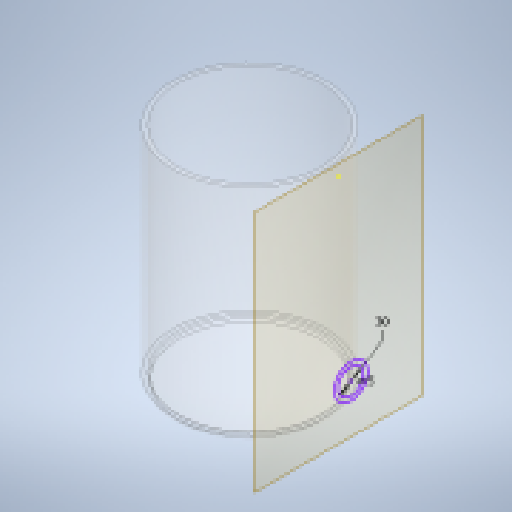
# Autodesk Inventor part: TANQUE
Saved by Autodesk Inventor 2025 (Build 290162000, 162)
## iProperties
Created: 2026-10-05
Part Number: TANQUE
Material: Plástico, transparente
Document SubType Name: Modeling
Designer: Projeto
Density: 1.188 g/cm^3
Appearance: Transparente - Claro
Author: Projeto
Autodesk Inventor part; units mm, degrees
ref_plane "XZ Plane" through (0, 0, 0) normal (0, 1, 0) x (-1, 0, 0)
ref_plane "XY Plane" through (0, 0, 0) normal (0, 0, 1) x (1, 0, 0)
sketch "Esboço1" plane through (0, 0, 0) normal (0, 0, 1) x (1, 0, 0)
  line L0 (-85, 0) -> (-85, -253)
  arc A0 (-85, -253) -> (-83, -255) centre (-83, -253) ccw
  line L1 (-83, -255) -> (0, -255)
  line L2 (-90, 0) -> (-90, -253)
  arc A1 (-90, -253) -> (-83, -260) centre (-83, -253) ccw
  line L3 (-83, -260) -> (0, -260)
  line L4 (0, -260) -> (0, -255)
  line L5 (0, -255) -> (0, 0) construction
  line L6 (-90, 0) -> (-85, 0)
  dimension "d0" = 5
  dimension "d1" = 180
  dimension "d2" = 260
  dimension "d3" = 2
  constraints: 14 end point, 4 point on circle, 2 centre point, 2 horizontal, 2 tangent, 2 vertical, 1 horizontal alignment, 1 perpendicular, 2 other
  measures "d0" distance between parallel lines of L2 L0
  measures "d1" diameter of L2 L5
  measures "d2" distance between parallel lines of L6 L3
  measures "d3" radius of A0
revolve "Revolução1" add sketch "Esboço1" angle 360 about axis through (0, -255, 0) along (0, 1, 0)
ref_plane "Work Plane1" through (105, 0, 0) normal (1, 0, 0) x (0, 1, 0)
sketch "Sketch2" plane through (105, 0, 0) normal (1, 0, 0) x (0, 1, 0)
  circle A0 centre (-232, 0) radius 15
  circle A1 centre (-232, 0) radius 20
  line L0 (-260, -83) -> (-260, 83) projected
  point P0 (0, 0)
  point P1 (-260, 0)
  dimension "d6" = 30
  dimension "d7" = 5
  dimension "d8" = 28
  constraints: 2 centre point, 1 coincident, 1 horizontal alignment, 1 midpoint
  measures "d6" diameter of A0
  measures "d7" radial gap between concentric circles of A1 A0
  measures "d8" distance from line of L0 A0.centre
extrude "Extrusion1" add sketch "Sketch2" against normal up to surface
sketch "Sketch3" plane through (105, -232, 0) normal (1, 0, 0) x (0, 0, -1)
  circle A0 centre (0, 0) radius 15 projected
  point P0 (0, 232)
extrude "Extrusion2" cut sketch "Sketch3" against normal blind 80
